Autodesk Fusion 360 part; units mm, degrees
(part 2 of 3)
sketch "草图8 (7)" plane through (0, 0, 8) normal (0, 0, 1) x (1, 0, 0) in component "05_CENTERED_FLAT_PSU_CRADLE_OPEN_INTAKE"
  line L0 (220.4, 198.92) -> (230.4, 198.92)
  line L1 (230.4, 198.92) -> (230.4, 208.92)
  line L2 (230.4, 208.92) -> (220.4, 208.92)
  line L3 (220.4, 208.92) -> (220.4, 198.92)
extrude "Short load foot to ground crossbar (3)" add sketch "草图8 (7)" along normal blind 16 bodies 24 in component "05_CENTERED_FLAT_PSU_CRADLE_OPEN_INTAKE"
ref_plane "工作平面9" through (0, 0, 30) normal (0, 0, 1) x (1, 0, 0) in component "05_CENTERED_FLAT_PSU_CRADLE_OPEN_INTAKE"
sketch "草图9 (7)" plane through (0, 0, 30) normal (0, 0, 1) x (1, 0, 0) in component "05_CENTERED_FLAT_PSU_CRADLE_OPEN_INTAKE"
  line L0 (75, 57.92) -> (77, 57.92)
  line L1 (77, 57.92) -> (77, 63.92)
  line L2 (77, 63.92) -> (75, 63.92)
  line L3 (75, 63.92) -> (75, 57.92)
ref_plane "工作平面10" through (0, 0, 30) normal (0, 0, 1) x (1, 0, 0) in component "05_CENTERED_FLAT_PSU_CRADLE_OPEN_INTAKE"
sketch "草图10 (4)" plane through (0, 0, 30) normal (0, 0, 1) x (1, 0, 0) in component "05_CENTERED_FLAT_PSU_CRADLE_OPEN_INTAKE"
  line L0 (75, 179.92) -> (77, 179.92)
  line L1 (77, 179.92) -> (77, 185.92)
  line L2 (77, 185.92) -> (75, 185.92)
  line L3 (75, 185.92) -> (75, 179.92)
extrude "PSU chassis edge locating stop (1)" add sketch "草图10 (4)" along normal blind 6 bodies 24 in component "05_CENTERED_FLAT_PSU_CRADLE_OPEN_INTAKE"
ref_plane "工作平面11" through (0, 0, 30) normal (0, 0, 1) x (1, 0, 0) in component "05_CENTERED_FLAT_PSU_CRADLE_OPEN_INTAKE"
sketch "草图11 (2)" plane through (0, 0, 30) normal (0, 0, 1) x (1, 0, 0) in component "05_CENTERED_FLAT_PSU_CRADLE_OPEN_INTAKE"
  line L0 (227.8, 57.92) -> (229.8, 57.92)
  line L1 (229.8, 57.92) -> (229.8, 63.92)
  line L2 (229.8, 63.92) -> (227.8, 63.92)
  line L3 (227.8, 63.92) -> (227.8, 57.92)
extrude "PSU chassis edge locating stop (2)" add sketch "草图11 (2)" along normal blind 6 bodies 24 in component "05_CENTERED_FLAT_PSU_CRADLE_OPEN_INTAKE"
ref_plane "工作平面12" through (0, 0, 30) normal (0, 0, 1) x (1, 0, 0) in component "05_CENTERED_FLAT_PSU_CRADLE_OPEN_INTAKE"
sketch "草图12" plane through (0, 0, 30) normal (0, 0, 1) x (1, 0, 0) in component "05_CENTERED_FLAT_PSU_CRADLE_OPEN_INTAKE"
  line L0 (227.8, 179.92) -> (229.8, 179.92)
  line L1 (229.8, 179.92) -> (229.8, 185.92)
  line L2 (229.8, 185.92) -> (227.8, 185.92)
  line L3 (227.8, 185.92) -> (227.8, 179.92)
extrude "PSU chassis edge locating stop (3)" add sketch "草图12" along normal blind 6 bodies 24 in component "05_CENTERED_FLAT_PSU_CRADLE_OPEN_INTAKE"
ref_plane "工作平面1" through (0, 0, 30) normal (0, 0, 1) x (1, 0, 0) in component "REF_PSU_FLAT_CENTERED_150x140x86"
sketch "草图1 (21)" plane through (0, 0, 30) normal (0, 0, 1) x (1, 0, 0) in component "REF_PSU_FLAT_CENTERED_150x140x86"
  line L0 (77.4, 51.92) -> (227.4, 51.92)
  line L1 (227.4, 51.92) -> (227.4, 191.92)
  line L2 (227.4, 191.92) -> (77.4, 191.92)
  line L3 (77.4, 191.92) -> (77.4, 51.92)
extrude "Horizontal PSU 150 wide x140 deep x86 high" add sketch "草图1 (21)" along normal blind 86 separate body makes body 25 in component "REF_PSU_FLAT_CENTERED_150x140x86"
ref_plane "工作平面1" through (0, 0, 29.7) normal (0, 0, 1) x (1, 0, 0) in component "REF_PSU_INTAKE_DOWN_MINUS_Z"
sketch "草图1 (22)" plane through (0, 0, 29.7) normal (0, 0, 1) x (1, 0, 0) in component "REF_PSU_INTAKE_DOWN_MINUS_Z"
  circle A0 centre (152.4, 121.92) radius 60
extrude "Downward-facing 120 mm intake marker - approximate" add sketch "草图1 (22)" along normal blind 0.3 separate body makes body 26 in component "REF_PSU_INTAKE_DOWN_MINUS_Z"
ref_plane "工作平面1" through (0, -191.92, 0) normal (0, 1, 0) x (0, 0, 1) in component "REF_PSU_REAR_EXHAUST_PLUS_Y"
sketch "草图1 (23)" plane through (0, -191.92, 0) normal (0, 1, 0) x (1, 0, 0) in component "REF_PSU_REAR_EXHAUST_PLUS_Y"
  line L0 (77.4, -30, 383.84) -> (227.4, -30, 383.84)
  line L1 (227.4, -30, 383.84) -> (227.4, -116, 383.84)
  line L2 (227.4, -116, 383.84) -> (77.4, -116, 383.84)
  line L3 (77.4, -116, 383.84) -> (77.4, -30, 383.84)
extrude "Rear exhaust face direction marker" add sketch "草图1 (23)" along normal blind 0.3 separate body contours L0 L1 L2 L3 in plane through (0, 191.92, 0) normal (0, 1, 0) makes body 27 in component "REF_PSU_REAR_EXHAUST_PLUS_Y"
ref_plane "工作平面13" through (0, 0, 30) normal (0, 0, 1) x (1, 0, 0) in component "05_CENTERED_FLAT_PSU_CRADLE_OPEN_INTAKE"
sketch "草图13" plane through (0, 0, 30) normal (0, 0, 1) x (1, 0, 0) in component "05_CENTERED_FLAT_PSU_CRADLE_OPEN_INTAKE"
  line L0 (75, 74) -> (77, 74)
  line L1 (77, 74) -> (77, 80)
  line L2 (77, 80) -> (75, 80)
  line L3 (75, 80) -> (75, 74)
extrude "PSU chassis edge locating stop" add sketch "草图13" along normal blind 6 bodies 24 in component "05_CENTERED_FLAT_PSU_CRADLE_OPEN_INTAKE"
ref_plane "工作平面14" through (0, 0, 30) normal (0, 0, 1) x (1, 0, 0) in component "05_CENTERED_FLAT_PSU_CRADLE_OPEN_INTAKE"
sketch "草图14" plane through (0, 0, 30) normal (0, 0, 1) x (1, 0, 0) in component "05_CENTERED_FLAT_PSU_CRADLE_OPEN_INTAKE"
  line L0 (75, 164) -> (77, 164)
  line L1 (77, 164) -> (77, 170)
  line L2 (77, 170) -> (75, 170)
  line L3 (75, 170) -> (75, 164)
extrude "PSU chassis edge locating stop (4)" add sketch "草图14" along normal blind 6 bodies 24 in component "05_CENTERED_FLAT_PSU_CRADLE_OPEN_INTAKE"
ref_plane "工作平面15" through (0, 0, 30) normal (0, 0, 1) x (1, 0, 0) in component "05_CENTERED_FLAT_PSU_CRADLE_OPEN_INTAKE"
sketch "草图15" plane through (0, 0, 30) normal (0, 0, 1) x (1, 0, 0) in component "05_CENTERED_FLAT_PSU_CRADLE_OPEN_INTAKE"
  line L0 (227.8, 74) -> (229.8, 74)
  line L1 (229.8, 74) -> (229.8, 80)
  line L2 (229.8, 80) -> (227.8, 80)
  line L3 (227.8, 80) -> (227.8, 74)
extrude "PSU chassis edge locating stop (5)" add sketch "草图15" along normal blind 6 bodies 24 in component "05_CENTERED_FLAT_PSU_CRADLE_OPEN_INTAKE"
ref_plane "工作平面16" through (0, 0, 30) normal (0, 0, 1) x (1, 0, 0) in component "05_CENTERED_FLAT_PSU_CRADLE_OPEN_INTAKE"
sketch "草图16" plane through (0, 0, 30) normal (0, 0, 1) x (1, 0, 0) in component "05_CENTERED_FLAT_PSU_CRADLE_OPEN_INTAKE"
  line L0 (227.8, 164) -> (229.8, 164)
  line L1 (229.8, 164) -> (229.8, 170)
  line L2 (229.8, 170) -> (227.8, 170)
  line L3 (227.8, 170) -> (227.8, 164)
extrude "PSU chassis edge locating stop (6)" add sketch "草图16" along normal blind 6 bodies 24 in component "05_CENTERED_FLAT_PSU_CRADLE_OPEN_INTAKE"
ref_plane "工作平面1" through (0, 10, 0) normal (0, 1, 0) x (0, 0, 1) in component "12_front_PCI_SUPPORT_FRAME"
sketch "草图1 (24)" plane through (0, 10, 0) normal (0, 1, 0) x (1, 0, 0) in component "12_front_PCI_SUPPORT_FRAME"
  line L0 (8.45, 0, -20) -> (152.1, 0, -20)
  line L1 (152.1, 0, -20) -> (152.1, -140, -20)
  line L2 (152.1, -140, -20) -> (-4, -140, -20)
  line L3 (-4, -140, -20) -> (8.45, 0, -20)
extrude "Front rear load frame" add sketch "草图1 (24)" along normal blind 16 separate body contours L0 L1 L2 L3 in plane through (0, -10, 0) normal (0, 1, 0) makes body 28 in component "12_front_PCI_SUPPORT_FRAME"
ref_plane "工作平面2" through (0, 0, 16) normal (0, 0, 1) x (1, 0, 0) in component "12_front_PCI_SUPPORT_FRAME"
sketch "草图2 (13)" plane through (0, 0, 16) normal (0, 0, 1) x (1, 0, 0) in component "12_front_PCI_SUPPORT_FRAME"
  line L0 (30, -11) -> (134, -11)
  line L1 (134, -11) -> (134, 7)
  line L2 (134, 7) -> (30, 7)
  line L3 (30, 7) -> (30, -11)
extrude "Open front frame window" cut sketch "草图2 (13)" along normal blind 108 bodies 28 in component "12_front_PCI_SUPPORT_FRAME"
ref_plane "工作平面3" through (0, 10, 0) normal (0, 1, 0) x (0, 0, 1) in component "12_front_PCI_SUPPORT_FRAME"
sketch "草图3 (12)" plane through (0, 10, 0) normal (0, 1, 0) x (1, 0, 0) in component "12_front_PCI_SUPPORT_FRAME"
  line L0 (30, -16, -20) -> (42, -16, -20)
  line L1 (42, -16, -20) -> (134, -112, -20)
  line L2 (134, -112, -20) -> (134, -124, -20)
  line L3 (134, -124, -20) -> (30, -16, -20)
extrude "Front diagonal brace" add sketch "草图3 (12)" along normal blind 16 contours L0 L1 L2 L3 in plane through (0, -10, 0) normal (0, 1, 0) bodies 28 in component "12_front_PCI_SUPPORT_FRAME"
ref_plane "工作平面1" through (0, 10, 0) normal (0, 1, 0) x (0, 0, 1) in component "12_front_CPU_SUPPORT_FRAME"
sketch "草图1 (25)" plane through (0, 10, 0) normal (0, 1, 0) x (1, 0, 0) in component "12_front_CPU_SUPPORT_FRAME"
  line L0 (152.7, 0, -20) -> (298.45, 0, -20)
  line L1 (298.45, 0, -20) -> (298.45, -140, -20)
  line L2 (298.45, -140, -20) -> (152.7, -140, -20)
  line L3 (152.7, -140, -20) -> (152.7, 0, -20)
extrude "Front rear load frame'" add sketch "草图1 (25)" along normal blind 16 separate body contours L0 L1 L2 L3 in plane through (0, -10, 0) normal (0, 1, 0) makes body 29 in component "12_front_CPU_SUPPORT_FRAME"
ref_plane "工作平面2" through (0, 0, 16) normal (0, 0, 1) x (1, 0, 0) in component "12_front_CPU_SUPPORT_FRAME"
sketch "草图2 (14)" plane through (0, 0, 16) normal (0, 0, 1) x (1, 0, 0) in component "12_front_CPU_SUPPORT_FRAME"
  line L0 (171, -11) -> (277, -11)
  line L1 (277, -11) -> (277, 7)
  line L2 (277, 7) -> (171, 7)
  line L3 (171, 7) -> (171, -11)
extrude "Open front frame window'" cut sketch "草图2 (14)" along normal blind 108 bodies 29 in component "12_front_CPU_SUPPORT_FRAME"
ref_plane "工作平面3" through (0, 10, 0) normal (0, 1, 0) x (0, 0, 1) in component "12_front_CPU_SUPPORT_FRAME"
sketch "草图3 (13)" plane through (0, 10, 0) normal (0, 1, 0) x (1, 0, 0) in component "12_front_CPU_SUPPORT_FRAME"
  line L0 (171, -16, -20) -> (183, -16, -20)
  line L1 (183, -16, -20) -> (277, -112, -20)
  line L2 (277, -112, -20) -> (277, -124, -20)
  line L3 (277, -124, -20) -> (171, -16, -20)
extrude "Front diagonal brace'" add sketch "草图3 (13)" along normal blind 16 contours L0 L1 L2 L3 in plane through (0, -10, 0) normal (0, 1, 0) bodies 29 in component "12_front_CPU_SUPPORT_FRAME"
ref_plane "工作平面1" through (0, -237.84, 0) normal (0, 1, 0) x (0, 0, 1) in component "12_rear_PCI_SUPPORT_FRAME"
sketch "草图1 (26)" plane through (0, -237.84, 0) normal (0, 1, 0) x (1, 0, 0) in component "12_rear_PCI_SUPPORT_FRAME"
  line L0 (8.45, 0, 475.68) -> (152.1, 0, 475.68)
  line L1 (152.1, 0, 475.68) -> (152.1, -140, 475.68)
  line L2 (152.1, -140, 475.68) -> (-4, -140, 475.68)
  line L3 (-4, -140, 475.68) -> (8.45, 0, 475.68)
extrude "Front rear load frame''" add sketch "草图1 (26)" along normal blind 16 separate body contours L0 L1 L2 L3 in plane through (0, 237.84, 0) normal (0, 1, 0) makes body 30 in component "12_rear_PCI_SUPPORT_FRAME"
ref_plane "工作平面2" through (0, 0, 16) normal (0, 0, 1) x (1, 0, 0) in component "12_rear_PCI_SUPPORT_FRAME"
sketch "草图2 (15)" plane through (0, 0, 16) normal (0, 0, 1) x (1, 0, 0) in component "12_rear_PCI_SUPPORT_FRAME"
  line L0 (30, 236.84) -> (277, 236.84)
  line L1 (277, 236.84) -> (277, 254.84)
  line L2 (277, 254.84) -> (30, 254.84)
  line L3 (30, 254.84) -> (30, 236.84)
extrude "Wide rear exhaust opening" cut sketch "草图2 (15)" along normal blind 109 bodies 30 in component "12_rear_PCI_SUPPORT_FRAME"
ref_plane "工作平面1" through (0, -237.84, 0) normal (0, 1, 0) x (0, 0, 1) in component "12_rear_CPU_SUPPORT_FRAME"
sketch "草图1 (27)" plane through (0, -237.84, 0) normal (0, 1, 0) x (1, 0, 0) in component "12_rear_CPU_SUPPORT_FRAME"
  line L0 (152.7, 0, 475.68) -> (298.45, 0, 475.68)
  line L1 (298.45, 0, 475.68) -> (298.45, -140, 475.68)
  line L2 (298.45, -140, 475.68) -> (152.7, -140, 475.68)
  line L3 (152.7, -140, 475.68) -> (152.7, 0, 475.68)
extrude "Front rear load frame'''" add sketch "草图1 (27)" along normal blind 16 separate body contours L0 L1 L2 L3 in plane through (0, 237.84, 0) normal (0, 1, 0) makes body 31 in component "12_rear_CPU_SUPPORT_FRAME"
ref_plane "工作平面2" through (0, 0, 16) normal (0, 0, 1) x (1, 0, 0) in component "12_rear_CPU_SUPPORT_FRAME"
sketch "草图2 (16)" plane through (0, 0, 16) normal (0, 0, 1) x (1, 0, 0) in component "12_rear_CPU_SUPPORT_FRAME"
  line L0 (30, 236.84) -> (277, 236.84)
  line L1 (277, 236.84) -> (277, 254.84)
  line L2 (277, 254.84) -> (30, 254.84)
  line L3 (30, 254.84) -> (30, 236.84)
extrude "Wide rear exhaust opening'" cut sketch "草图2 (16)" along normal blind 109 bodies 31 in component "12_rear_CPU_SUPPORT_FRAME"
ref_plane "工作平面2" through (0, 0, -0.1) normal (0, 0, 1) x (1, 0, 0) in component "04_front_GROUND_BAR_290mm_FLAT_PSU"
sketch "草图2 (17)" plane through (0, 0, -0.1) normal (0, 0, 1) x (1, 0, 0) in component "04_front_GROUND_BAR_290mm_FLAT_PSU"
  line L0 (8, 20) -> (24.45, 20)
  line L1 (24.45, 20) -> (24.45, 220)
  line L2 (24.45, 220) -> (8, 220)
  line L3 (8, 220) -> (8, 20)
extrude "Butt joint to PCI floor runner" cut sketch "草图2 (17)" along normal blind 8.2 bodies 22 in component "04_front_GROUND_BAR_290mm_FLAT_PSU"
ref_plane "工作平面3" through (0, 0, -0.1) normal (0, 0, 1) x (1, 0, 0) in component "04_front_GROUND_BAR_290mm_FLAT_PSU"
sketch "草图3 (14)" plane through (0, 0, -0.1) normal (0, 0, 1) x (1, 0, 0) in component "04_front_GROUND_BAR_290mm_FLAT_PSU"
  line L0 (282.45, 20) -> (299, 20)
  line L1 (299, 20) -> (299, 220)
  line L2 (299, 220) -> (282.45, 220)
  line L3 (282.45, 220) -> (282.45, 20)
extrude "Butt joint to CPU floor runner" cut sketch "草图3 (14)" along normal blind 8.2 bodies 22 in component "04_front_GROUND_BAR_290mm_FLAT_PSU"
ref_plane "工作平面2" through (0, 0, -0.1) normal (0, 0, 1) x (1, 0, 0) in component "04_rear_GROUND_BAR_290mm_FLAT_PSU"
sketch "草图2 (18)" plane through (0, 0, -0.1) normal (0, 0, 1) x (1, 0, 0) in component "04_rear_GROUND_BAR_290mm_FLAT_PSU"
  line L0 (8, 20) -> (24.45, 20)
  line L1 (24.45, 20) -> (24.45, 220)
  line L2 (24.45, 220) -> (8, 220)
  line L3 (8, 220) -> (8, 20)
extrude "Butt joint to PCI floor runner'" cut sketch "草图2 (18)" along normal blind 8.2 bodies 23 in component "04_rear_GROUND_BAR_290mm_FLAT_PSU"
ref_plane "工作平面3" through (0, 0, -0.1) normal (0, 0, 1) x (1, 0, 0) in component "04_rear_GROUND_BAR_290mm_FLAT_PSU"
sketch "草图3 (15)" plane through (0, 0, -0.1) normal (0, 0, 1) x (1, 0, 0) in component "04_rear_GROUND_BAR_290mm_FLAT_PSU"
  line L0 (282.45, 20) -> (299, 20)
  line L1 (299, 20) -> (299, 220)
  line L2 (299, 220) -> (282.45, 220)
  line L3 (282.45, 220) -> (282.45, 20)
extrude "Butt joint to CPU floor runner'" cut sketch "草图3 (15)" along normal blind 8.2 bodies 23 in component "04_rear_GROUND_BAR_290mm_FLAT_PSU"
ref_plane "工作平面4" through (0, 0, 128) normal (0, 0, 1) x (1, 0, 0) in component "12_front_PCI_SUPPORT_FRAME"
sketch "草图4 (12)" plane through (0, 0, 128) normal (0, 0, 1) x (1, 0, 0) in component "12_front_PCI_SUPPORT_FRAME"
  line L0 (14, -2.65) -> (281.45, -2.65)
  line L1 (281.45, -2.65) -> (281.45, 6.01)
  line L2 (281.45, 6.01) -> (14, 6.01)
  line L3 (14, 6.01) -> (14, -2.65)
extrude "Seat for front motherboard beam rib" cut sketch "草图4 (12)" along normal blind 12.01 bodies 28 in component "12_front_PCI_SUPPORT_FRAME"
ref_plane "工作平面4" through (0, 0, 128) normal (0, 0, 1) x (1, 0, 0) in component "12_front_CPU_SUPPORT_FRAME"
sketch "草图4 (13)" plane through (0, 0, 128) normal (0, 0, 1) x (1, 0, 0) in component "12_front_CPU_SUPPORT_FRAME"
  line L0 (14, -2.65) -> (281.45, -2.65)
  line L1 (281.45, -2.65) -> (281.45, 6.01)
  line L2 (281.45, 6.01) -> (14, 6.01)
  line L3 (14, 6.01) -> (14, -2.65)
extrude "Seat for front motherboard beam rib'" cut sketch "草图4 (13)" along normal blind 12.01 bodies 29 in component "12_front_CPU_SUPPORT_FRAME"
ref_plane "工作平面3" through (0, 0, 128) normal (0, 0, 1) x (1, 0, 0) in component "12_rear_PCI_SUPPORT_FRAME"
sketch "草图3 (16)" plane through (0, 0, 128) normal (0, 0, 1) x (1, 0, 0) in component "12_rear_PCI_SUPPORT_FRAME"
  line L0 (14, 237.83) -> (281.45, 237.83)
  line L1 (281.45, 237.83) -> (281.45, 242.68)
  line L2 (281.45, 242.68) -> (14, 242.68)
  line L3 (14, 242.68) -> (14, 237.83)
extrude "Seat for rear motherboard beam rib" cut sketch "草图3 (16)" along normal blind 12.01 bodies 30 in component "12_rear_PCI_SUPPORT_FRAME"
ref_plane "工作平面3" through (0, 0, 128) normal (0, 0, 1) x (1, 0, 0) in component "12_rear_CPU_SUPPORT_FRAME"
sketch "草图3 (17)" plane through (0, 0, 128) normal (0, 0, 1) x (1, 0, 0) in component "12_rear_CPU_SUPPORT_FRAME"
  line L0 (14, 237.83) -> (281.45, 237.83)
  line L1 (281.45, 237.83) -> (281.45, 242.68)
  line L2 (281.45, 242.68) -> (14, 242.68)
  line L3 (14, 242.68) -> (14, 237.83)
extrude "Seat for rear motherboard beam rib'" cut sketch "草图3 (17)" along normal blind 12.01 bodies 31 in component "12_rear_CPU_SUPPORT_FRAME"
ref_plane "工作平面1" through (0, 0, 140) normal (0, 0, 1) x (1, 0, 0) in component "07_GPU_REINFORCED_REAR_TOWER"
sketch "草图1 (28)" plane through (0, 0, 140) normal (0, 0, 1) x (1, 0, 0) in component "07_GPU_REINFORCED_REAR_TOWER"
  line L0 (70, 244) -> (174, 244)
  line L1 (174, 244) -> (174, 282)
  line L2 (174, 282) -> (70, 282)
  line L3 (70, 282) -> (70, 244)
extrude "Rear frame mounted structural foot" add sketch "草图1 (28)" along normal blind 8 separate body makes body 32 in component "07_GPU_REINFORCED_REAR_TOWER"
ref_plane "工作平面2" through (0, 0, 148) normal (0, 0, 1) x (1, 0, 0) in component "07_GPU_REINFORCED_REAR_TOWER"
sketch "草图2 (19)" plane through (0, 0, 148) normal (0, 0, 1) x (1, 0, 0) in component "07_GPU_REINFORCED_REAR_TOWER"
  line L0 (70, 260) -> (174, 260)
  line L1 (174, 260) -> (174, 270)
  line L2 (174, 270) -> (70, 270)
  line L3 (70, 270) -> (70, 260)
extrude "10 mm rear tower wall" add sketch "草图2 (19)" along normal blind 154 bodies 32 in component "07_GPU_REINFORCED_REAR_TOWER"
ref_plane "工作平面3" through (0, 0, 170) normal (0, 0, 1) x (1, 0, 0) in component "07_GPU_REINFORCED_REAR_TOWER"
sketch "草图3 (18)" plane through (0, 0, 170) normal (0, 0, 1) x (1, 0, 0) in component "07_GPU_REINFORCED_REAR_TOWER"
  line L0 (88, 259.9) -> (156, 259.9)
  line L1 (156, 259.9) -> (156, 270.1)
  line L2 (156, 270.1) -> (88, 270.1)
  line L3 (88, 270.1) -> (88, 259.9)
extrude "Unobstructed display connector window" cut sketch "草图3 (18)" along normal blind 88 bodies 32 in component "07_GPU_REINFORCED_REAR_TOWER"
ref_plane "工作平面4" through (70, 0, 0) normal (1, 0, 0) x (0, 1, 0) in component "07_GPU_REINFORCED_REAR_TOWER"
sketch "草图4 (14)" plane through (70, 0, 0) normal (1, 0, 0) x (0, 0, -1) in component "07_GPU_REINFORCED_REAR_TOWER"
  line L0 (-148, 270) -> (-148, 282)
  line L1 (-148, 282) -> (-212, 270)
  line L2 (-212, 270) -> (-148, 270)
extrude "Tower foot triangular rear gusset" add sketch "草图4 (14)" along normal blind 10 bodies 32 in component "07_GPU_REINFORCED_REAR_TOWER"
ref_plane "工作平面5" through (164, 0, 0) normal (1, 0, 0) x (0, 1, 0) in component "07_GPU_REINFORCED_REAR_TOWER"
sketch "草图5 (11)" plane through (164, 0, 0) normal (1, 0, 0) x (0, 0, -1) in component "07_GPU_REINFORCED_REAR_TOWER"
  line L0 (-148, 270) -> (-148, 282)
  line L1 (-148, 282) -> (-212, 270)
  line L2 (-212, 270) -> (-148, 270)
extrude "Tower foot triangular rear gusset (1)" add sketch "草图5 (11)" along normal blind 10 bodies 32 in component "07_GPU_REINFORCED_REAR_TOWER"
ref_plane "工作平面6" through (0, -260, 0) normal (0, 1, 0) x (0, 0, 1) in component "07_GPU_REINFORCED_REAR_TOWER"
sketch "草图6 (11)" plane through (0, -260, 0) normal (0, 1, 0) x (1, 0, 0) in component "07_GPU_REINFORCED_REAR_TOWER"
  circle A0 through (81.7, -262, 520) (79.15, -260.5278, 520) (79.15, -263.4722, 520)
extrude "Upper carrier height adjustment lower end" cut sketch "草图6 (11)" along normal blind 10 contours A0 in plane through (0, 260, 0) normal (0, 1, 0) bodies 32 in component "07_GPU_REINFORCED_REAR_TOWER"
ref_plane "工作平面7" through (0, -260, 0) normal (0, 1, 0) x (0, 0, 1) in component "07_GPU_REINFORCED_REAR_TOWER"
sketch "草图7 (9)" plane through (0, -260, 0) normal (0, 1, 0) x (1, 0, 0) in component "07_GPU_REINFORCED_REAR_TOWER"
  circle A0 through (81.7, -292, 520) (79.15, -290.5278, 520) (79.15, -293.4722, 520)
extrude "Upper carrier height adjustment upper end" cut sketch "草图7 (9)" along normal blind 10 contours A0 in plane through (0, 260, 0) normal (0, 1, 0) bodies 32 in component "07_GPU_REINFORCED_REAR_TOWER"
ref_plane "工作平面8" through (0, -260, 0) normal (0, 1, 0) x (0, 0, 1) in component "07_GPU_REINFORCED_REAR_TOWER"
sketch "草图8 (8)" plane through (0, -260, 0) normal (0, 1, 0) x (1, 0, 0) in component "07_GPU_REINFORCED_REAR_TOWER"
  line L0 (78.3, -262, 520) -> (81.7, -262, 520)
  line L1 (81.7, -262, 520) -> (81.7, -292, 520)
  line L2 (81.7, -292, 520) -> (78.3, -292, 520)
  line L3 (78.3, -292, 520) -> (78.3, -262, 520)
extrude "Upper carrier height adjustment web" cut sketch "草图8 (8)" along normal blind 10 contours L0 L1 L2 L3 in plane through (0, 260, 0) normal (0, 1, 0) bodies 32 in component "07_GPU_REINFORCED_REAR_TOWER"
ref_plane "工作平面9" through (0, -260, 0) normal (0, 1, 0) x (0, 0, 1) in component "07_GPU_REINFORCED_REAR_TOWER"
sketch "草图9 (8)" plane through (0, -260, 0) normal (0, 1, 0) x (1, 0, 0) in component "07_GPU_REINFORCED_REAR_TOWER"
  circle A0 through (81.7, -151, 520) (79.15, -149.5278, 520) (79.15, -152.4722, 520)
extrude "Lower tab receiver height adjustment lower end" cut sketch "草图9 (8)" along normal blind 10 contours A0 in plane through (0, 260, 0) normal (0, 1, 0) bodies 32 in component "07_GPU_REINFORCED_REAR_TOWER"
ref_plane "工作平面10" through (0, -260, 0) normal (0, 1, 0) x (0, 0, 1) in component "07_GPU_REINFORCED_REAR_TOWER"
sketch "草图10 (5)" plane through (0, -260, 0) normal (0, 1, 0) x (1, 0, 0) in component "07_GPU_REINFORCED_REAR_TOWER"
  circle A0 through (81.7, -165, 520) (79.15, -163.5278, 520) (79.15, -166.4722, 520)
extrude "Lower tab receiver height adjustment upper end" cut sketch "草图10 (5)" along normal blind 10 contours A0 in plane through (0, 260, 0) normal (0, 1, 0) bodies 32 in component "07_GPU_REINFORCED_REAR_TOWER"
ref_plane "工作平面11" through (0, -260, 0) normal (0, 1, 0) x (0, 0, 1) in component "07_GPU_REINFORCED_REAR_TOWER"
sketch "草图11 (3)" plane through (0, -260, 0) normal (0, 1, 0) x (1, 0, 0) in component "07_GPU_REINFORCED_REAR_TOWER"
  line L0 (78.3, -151, 520) -> (81.7, -151, 520)
  line L1 (81.7, -151, 520) -> (81.7, -165, 520)
  line L2 (81.7, -165, 520) -> (78.3, -165, 520)
  line L3 (78.3, -165, 520) -> (78.3, -151, 520)
extrude "Lower tab receiver height adjustment web" cut sketch "草图11 (3)" along normal blind 10 contours L0 L1 L2 L3 in plane through (0, 260, 0) normal (0, 1, 0) bodies 32 in component "07_GPU_REINFORCED_REAR_TOWER"
ref_plane "工作平面12" through (0, -260, 0) normal (0, 1, 0) x (0, 0, 1) in component "07_GPU_REINFORCED_REAR_TOWER"
sketch "草图12 (2)" plane through (0, -260, 0) normal (0, 1, 0) x (1, 0, 0) in component "07_GPU_REINFORCED_REAR_TOWER"
  circle A0 through (165.7, -262, 520) (163.15, -260.5278, 520) (163.15, -263.4722, 520)
extrude "Upper carrier height adjustment lower end (1)" cut sketch "草图12 (2)" along normal blind 10 contours A0 in plane through (0, 260, 0) normal (0, 1, 0) bodies 32 in component "07_GPU_REINFORCED_REAR_TOWER"
ref_plane "工作平面13" through (0, -260, 0) normal (0, 1, 0) x (0, 0, 1) in component "07_GPU_REINFORCED_REAR_TOWER"
sketch "草图13 (2)" plane through (0, -260, 0) normal (0, 1, 0) x (1, 0, 0) in component "07_GPU_REINFORCED_REAR_TOWER"
  circle A0 through (165.7, -292, 520) (163.15, -290.5278, 520) (163.15, -293.4722, 520)
extrude "Upper carrier height adjustment upper end (1)" cut sketch "草图13 (2)" along normal blind 10 contours A0 in plane through (0, 260, 0) normal (0, 1, 0) bodies 32 in component "07_GPU_REINFORCED_REAR_TOWER"
ref_plane "工作平面14" through (0, -260, 0) normal (0, 1, 0) x (0, 0, 1) in component "07_GPU_REINFORCED_REAR_TOWER"
sketch "草图14 (2)" plane through (0, -260, 0) normal (0, 1, 0) x (1, 0, 0) in component "07_GPU_REINFORCED_REAR_TOWER"
  line L0 (162.3, -262, 520) -> (165.7, -262, 520)
  line L1 (165.7, -262, 520) -> (165.7, -292, 520)
  line L2 (165.7, -292, 520) -> (162.3, -292, 520)
  line L3 (162.3, -292, 520) -> (162.3, -262, 520)
extrude "Upper carrier height adjustment web (1)" cut sketch "草图14 (2)" along normal blind 10 contours L0 L1 L2 L3 in plane through (0, 260, 0) normal (0, 1, 0) bodies 32 in component "07_GPU_REINFORCED_REAR_TOWER"
ref_plane "工作平面15" through (0, -260, 0) normal (0, 1, 0) x (0, 0, 1) in component "07_GPU_REINFORCED_REAR_TOWER"
sketch "草图15 (2)" plane through (0, -260, 0) normal (0, 1, 0) x (1, 0, 0) in component "07_GPU_REINFORCED_REAR_TOWER"
  circle A0 through (165.7, -151, 520) (163.15, -149.5278, 520) (163.15, -152.4722, 520)
extrude "Lower tab receiver height adjustment lower end (1)" cut sketch "草图15 (2)" along normal blind 10 contours A0 in plane through (0, 260, 0) normal (0, 1, 0) bodies 32 in component "07_GPU_REINFORCED_REAR_TOWER"
ref_plane "工作平面16" through (0, -260, 0) normal (0, 1, 0) x (0, 0, 1) in component "07_GPU_REINFORCED_REAR_TOWER"
sketch "草图16 (2)" plane through (0, -260, 0) normal (0, 1, 0) x (1, 0, 0) in component "07_GPU_REINFORCED_REAR_TOWER"
  circle A0 through (165.7, -165, 520) (163.15, -163.5278, 520) (163.15, -166.4722, 520)
extrude "Lower tab receiver height adjustment upper end (1)" cut sketch "草图16 (2)" along normal blind 10 contours A0 in plane through (0, 260, 0) normal (0, 1, 0) bodies 32 in component "07_GPU_REINFORCED_REAR_TOWER"
ref_plane "工作平面17" through (0, -260, 0) normal (0, 1, 0) x (0, 0, 1) in component "07_GPU_REINFORCED_REAR_TOWER"
sketch "草图17" plane through (0, -260, 0) normal (0, 1, 0) x (1, 0, 0) in component "07_GPU_REINFORCED_REAR_TOWER"
  line L0 (162.3, -151, 520) -> (165.7, -151, 520)
  line L1 (165.7, -151, 520) -> (165.7, -165, 520)
  line L2 (165.7, -165, 520) -> (162.3, -165, 520)
  line L3 (162.3, -165, 520) -> (162.3, -151, 520)
extrude "Lower tab receiver height adjustment web (1)" cut sketch "草图17" along normal blind 10 contours L0 L1 L2 L3 in plane through (0, 260, 0) normal (0, 1, 0) bodies 32 in component "07_GPU_REINFORCED_REAR_TOWER"
ref_plane "工作平面18" through (0, 0, 140) normal (0, 0, 1) x (1, 0, 0) in component "07_GPU_REINFORCED_REAR_TOWER"
sketch "草图18" plane through (0, 0, 140) normal (0, 0, 1) x (1, 0, 0) in component "07_GPU_REINFORCED_REAR_TOWER"
  circle A0 centre (80, 248.5) radius 1.7
extrude "Rear frame mounting screw clearance" cut sketch "草图18" along normal blind 8 bodies 32 in component "07_GPU_REINFORCED_REAR_TOWER"
ref_plane "工作平面4" through (0, 0, 133.5) normal (0, 0, 1) x (1, 0, 0) in component "12_rear_PCI_SUPPORT_FRAME"
sketch "草图4 (15)" plane through (0, 0, 133.5) normal (0, 0, 1) x (1, 0, 0) in component "12_rear_PCI_SUPPORT_FRAME"
  circle A0 centre (80, 248.5) radius 2.3
extrude "Trial M3 H4.5 OD5 insert pocket" cut sketch "草图4 (15)" along normal blind 6.5 bodies 30 in component "12_rear_PCI_SUPPORT_FRAME"
ref_plane "工作平面19" through (0, 0, 140) normal (0, 0, 1) x (1, 0, 0) in component "07_GPU_REINFORCED_REAR_TOWER"
sketch "草图19" plane through (0, 0, 140) normal (0, 0, 1) x (1, 0, 0) in component "07_GPU_REINFORCED_REAR_TOWER"
  circle A0 centre (140, 248.5) radius 1.7
extrude "Rear frame mounting screw clearance (1)" cut sketch "草图19" along normal blind 8 bodies 32 in component "07_GPU_REINFORCED_REAR_TOWER"
ref_plane "工作平面5" through (0, 0, 133.5) normal (0, 0, 1) x (1, 0, 0) in component "12_rear_PCI_SUPPORT_FRAME"
sketch "草图5 (12)" plane through (0, 0, 133.5) normal (0, 0, 1) x (1, 0, 0) in component "12_rear_PCI_SUPPORT_FRAME"
  circle A0 centre (140, 248.5) radius 2.3
extrude "Trial M3 H4.5 OD5 insert pocket (1)" cut sketch "草图5 (12)" along normal blind 6.5 bodies 30 in component "12_rear_PCI_SUPPORT_FRAME"
ref_plane "工作平面20" through (0, 0, 140) normal (0, 0, 1) x (1, 0, 0) in component "07_GPU_REINFORCED_REAR_TOWER"
sketch "草图20" plane through (0, 0, 140) normal (0, 0, 1) x (1, 0, 0) in component "07_GPU_REINFORCED_REAR_TOWER"
  circle A0 centre (158, 248.5) radius 1.7
extrude "CPU rear frame screw clearance" cut sketch "草图20" along normal blind 8 bodies 32 in component "07_GPU_REINFORCED_REAR_TOWER"
ref_plane "工作平面4" through (0, 0, 133.5) normal (0, 0, 1) x (1, 0, 0) in component "12_rear_CPU_SUPPORT_FRAME"
sketch "草图4 (16)" plane through (0, 0, 133.5) normal (0, 0, 1) x (1, 0, 0) in component "12_rear_CPU_SUPPORT_FRAME"
  circle A0 centre (158, 248.5) radius 2.3
extrude "Trial M3 H4.5 OD5 insert pocket'" cut sketch "草图4 (16)" along normal blind 6.5 bodies 31 in component "12_rear_CPU_SUPPORT_FRAME"
ref_plane "工作平面1" through (0, 0, 260) normal (0, 0, 1) x (1, 0, 0) in component "08_GPU_UPPER_EAR_LEDGE_ADJUSTABLE"
sketch "草图1 (29)" plane through (0, 0, 260) normal (0, 0, 1) x (1, 0, 0) in component "08_GPU_UPPER_EAR_LEDGE_ADJUSTABLE"
  line L0 (74, 254) -> (170, 254)
  line L1 (170, 254) -> (170, 260)
  line L2 (170, 260) -> (74, 260)
  line L3 (74, 260) -> (74, 254)
extrude "Upper sliding mounting plate" add sketch "草图1 (29)" along normal blind 36 separate body makes body 33 in component "08_GPU_UPPER_EAR_LEDGE_ADJUSTABLE"
ref_plane "工作平面2" through (0, 0, 272) normal (0, 0, 1) x (1, 0, 0) in component "08_GPU_UPPER_EAR_LEDGE_ADJUSTABLE"
sketch "草图2 (20)" plane through (0, 0, 272) normal (0, 0, 1) x (1, 0, 0) in component "08_GPU_UPPER_EAR_LEDGE_ADJUSTABLE"
  line L0 (84, 244.84) -> (154, 244.84)
  line L1 (154, 244.84) -> (154, 254)
  line L2 (154, 254) -> (84, 254)
  line L3 (84, 254) -> (84, 244.84)
extrude "10 mm horizontal ear bearing ledge" add sketch "草图2 (20)" along normal blind 10 bodies 33 in component "08_GPU_UPPER_EAR_LEDGE_ADJUSTABLE"
ref_plane "工作平面3" through (84, 0, 0) normal (1, 0, 0) x (0, 1, 0) in component "08_GPU_UPPER_EAR_LEDGE_ADJUSTABLE"
sketch "草图3 (19)" plane through (84, 0, 0) normal (1, 0, 0) x (0, 0, -1) in component "08_GPU_UPPER_EAR_LEDGE_ADJUSTABLE"
  line L0 (-272, 244.84) -> (-262, 254)
  line L1 (-262, 254) -> (-272, 254)
  line L2 (-272, 254) -> (-272, 244.84)
extrude "Under-ledge triangular gusset" add sketch "草图3 (19)" along normal blind 6 bodies 33 in component "08_GPU_UPPER_EAR_LEDGE_ADJUSTABLE"
ref_plane "工作平面4" through (148, 0, 0) normal (1, 0, 0) x (0, 1, 0) in component "08_GPU_UPPER_EAR_LEDGE_ADJUSTABLE"
sketch "草图4 (17)" plane through (148, 0, 0) normal (1, 0, 0) x (0, 0, -1) in component "08_GPU_UPPER_EAR_LEDGE_ADJUSTABLE"
  line L0 (-272, 244.84) -> (-262, 254)
  line L1 (-262, 254) -> (-272, 254)
  line L2 (-272, 254) -> (-272, 244.84)
extrude "Under-ledge triangular gusset (1)" add sketch "草图4 (17)" along normal blind 6 bodies 33 in component "08_GPU_UPPER_EAR_LEDGE_ADJUSTABLE"
ref_plane "工作平面5" through (0, -254, 0) normal (0, 1, 0) x (0, 0, 1) in component "08_GPU_UPPER_EAR_LEDGE_ADJUSTABLE"
sketch "草图5 (13)" plane through (0, -254, 0) normal (0, 1, 0) x (1, 0, 0) in component "08_GPU_UPPER_EAR_LEDGE_ADJUSTABLE"
  circle A0 through (81.7, -276, 508) (79.15, -274.5278, 508) (79.15, -277.4722, 508)
extrude "M3 carrier clamp through hole" cut sketch "草图5 (13)" along normal blind 6 contours A0 in plane through (0, 254, 0) normal (0, 1, 0) bodies 33 in component "08_GPU_UPPER_EAR_LEDGE_ADJUSTABLE"
ref_plane "工作平面6" through (0, -254, 0) normal (0, 1, 0) x (0, 0, 1) in component "08_GPU_UPPER_EAR_LEDGE_ADJUSTABLE"
sketch "草图6 (12)" plane through (0, -254, 0) normal (0, 1, 0) x (1, 0, 0) in component "08_GPU_UPPER_EAR_LEDGE_ADJUSTABLE"
  circle A0 through (165.7, -276, 508) (163.15, -274.5278, 508) (163.15, -277.4722, 508)
extrude "M3 carrier clamp through hole (1)" cut sketch "草图6 (12)" along normal blind 6 contours A0 in plane through (0, 254, 0) normal (0, 1, 0) bodies 33 in component "08_GPU_UPPER_EAR_LEDGE_ADJUSTABLE"
ref_plane "工作平面7" through (0, 0, 275.5) normal (0, 0, 1) x (1, 0, 0) in component "08_GPU_UPPER_EAR_LEDGE_ADJUSTABLE"
sketch "草图7 (10)" plane through (0, 0, 275.5) normal (0, 0, 1) x (1, 0, 0) in component "08_GPU_UPPER_EAR_LEDGE_ADJUSTABLE"
  circle A0 centre (100, 249.5) radius 2.3
extrude "Trial M3 short insert for graphics card ear" cut sketch "草图7 (10)" along normal blind 6.5 bodies 33 in component "08_GPU_UPPER_EAR_LEDGE_ADJUSTABLE"
ref_plane "工作平面8" through (0, 0, 275.5) normal (0, 0, 1) x (1, 0, 0) in component "08_GPU_UPPER_EAR_LEDGE_ADJUSTABLE"
sketch "草图8 (9)" plane through (0, 0, 275.5) normal (0, 0, 1) x (1, 0, 0) in component "08_GPU_UPPER_EAR_LEDGE_ADJUSTABLE"
  circle A0 centre (120, 249.5) radius 2.3
extrude "Trial M3 short insert for graphics card ear (1)" cut sketch "草图8 (9)" along normal blind 6.5 bodies 33 in component "08_GPU_UPPER_EAR_LEDGE_ADJUSTABLE"
ref_plane "工作平面1" through (0, 0, 146) normal (0, 0, 1) x (1, 0, 0) in component "08_GPU_LOWER_TWO_TAB_RECEIVER_ADJUSTABLE"
sketch "草图1 (30)" plane through (0, 0, 146) normal (0, 0, 1) x (1, 0, 0) in component "08_GPU_LOWER_TWO_TAB_RECEIVER_ADJUSTABLE"
  line L0 (74, 254) -> (170, 254)
  line L1 (170, 254) -> (170, 260)
  line L2 (170, 260) -> (74, 260)
  line L3 (74, 260) -> (74, 254)
extrude "Lower sliding receiver back plate" add sketch "草图1 (30)" along normal blind 18 separate body makes body 34 in component "08_GPU_LOWER_TWO_TAB_RECEIVER_ADJUSTABLE"
ref_plane "工作平面2" through (0, 0, 146) normal (0, 0, 1) x (1, 0, 0) in component "08_GPU_LOWER_TWO_TAB_RECEIVER_ADJUSTABLE"
sketch "草图2 (21)" plane through (0, 0, 146) normal (0, 0, 1) x (1, 0, 0) in component "08_GPU_LOWER_TWO_TAB_RECEIVER_ADJUSTABLE"
  line L0 (84, 244.84) -> (140, 244.84)
  line L1 (140, 244.84) -> (140, 254)
  line L2 (140, 254) -> (84, 254)
  line L3 (84, 254) -> (84, 244.84)
extrude "Lower metal tab guide block" add sketch "草图2 (21)" along normal blind 12 bodies 34 in component "08_GPU_LOWER_TWO_TAB_RECEIVER_ADJUSTABLE"
ref_plane "工作平面3" through (0, 0, 145.9) normal (0, 0, 1) x (1, 0, 0) in component "08_GPU_LOWER_TWO_TAB_RECEIVER_ADJUSTABLE"
sketch "草图3 (20)" plane through (0, 0, 145.9) normal (0, 0, 1) x (1, 0, 0) in component "08_GPU_LOWER_TWO_TAB_RECEIVER_ADJUSTABLE"
  line L0 (89, 246.3) -> (103, 246.3)
  line L1 (103, 246.3) -> (103, 248.7)
  line L2 (103, 248.7) -> (89, 248.7)
  line L3 (89, 248.7) -> (89, 246.3)
extrude "Open bottom tab slot - nominal position" cut sketch "草图3 (20)" along normal blind 12.2 bodies 34 in component "08_GPU_LOWER_TWO_TAB_RECEIVER_ADJUSTABLE"
ref_plane "工作平面4" through (0, 0, 145.9) normal (0, 0, 1) x (1, 0, 0) in component "08_GPU_LOWER_TWO_TAB_RECEIVER_ADJUSTABLE"
sketch "草图4 (18)" plane through (0, 0, 145.9) normal (0, 0, 1) x (1, 0, 0) in component "08_GPU_LOWER_TWO_TAB_RECEIVER_ADJUSTABLE"
  line L0 (109, 246.3) -> (123, 246.3)
  line L1 (123, 246.3) -> (123, 248.7)
  line L2 (123, 248.7) -> (109, 248.7)
  line L3 (109, 248.7) -> (109, 246.3)
extrude "Open bottom tab slot - nominal position (1)" cut sketch "草图4 (18)" along normal blind 12.2 bodies 34 in component "08_GPU_LOWER_TWO_TAB_RECEIVER_ADJUSTABLE"
ref_plane "工作平面5" through (0, -254, 0) normal (0, 1, 0) x (0, 0, 1) in component "08_GPU_LOWER_TWO_TAB_RECEIVER_ADJUSTABLE"
sketch "草图5 (14)" plane through (0, -254, 0) normal (0, 1, 0) x (1, 0, 0) in component "08_GPU_LOWER_TWO_TAB_RECEIVER_ADJUSTABLE"
  circle A0 through (81.7, -157, 508) (79.15, -155.5278, 508) (79.15, -158.4722, 508)
extrude "M3 lower receiver clamp through hole" cut sketch "草图5 (14)" along normal blind 6 contours A0 in plane through (0, 254, 0) normal (0, 1, 0) bodies 34 in component "08_GPU_LOWER_TWO_TAB_RECEIVER_ADJUSTABLE"
ref_plane "工作平面6" through (0, -254, 0) normal (0, 1, 0) x (0, 0, 1) in component "08_GPU_LOWER_TWO_TAB_RECEIVER_ADJUSTABLE"
sketch "草图6 (13)" plane through (0, -254, 0) normal (0, 1, 0) x (1, 0, 0) in component "08_GPU_LOWER_TWO_TAB_RECEIVER_ADJUSTABLE"
  circle A0 through (165.7, -157, 508) (163.15, -155.5278, 508) (163.15, -158.4722, 508)
extrude "M3 lower receiver clamp through hole (1)" cut sketch "草图6 (13)" along normal blind 6 contours A0 in plane through (0, 254, 0) normal (0, 1, 0) bodies 34 in component "08_GPU_LOWER_TWO_TAB_RECEIVER_ADJUSTABLE"
ref_plane "工作平面7" through (0, 0, 145.9) normal (0, 0, 1) x (1, 0, 0) in component "08_GPU_LOWER_TWO_TAB_RECEIVER_ADJUSTABLE"
sketch "草图7 (11)" plane through (0, 0, 145.9) normal (0, 0, 1) x (1, 0, 0) in component "08_GPU_LOWER_TWO_TAB_RECEIVER_ADJUSTABLE"
  line L0 (73, 244) -> (171, 244)
  line L1 (171, 244) -> (171, 260.1)
  line L2 (171, 260.1) -> (73, 260.1)
  line L3 (73, 260.1) -> (73, 244)
extrude "Receiver clearance above structural foot" cut sketch "草图7 (11)" along normal blind 2.1 bodies 34 in component "08_GPU_LOWER_TWO_TAB_RECEIVER_ADJUSTABLE"
ref_plane "工作平面21" through (0, 0, 139.9) normal (0, 0, 1) x (1, 0, 0) in component "07_GPU_REINFORCED_REAR_TOWER"
sketch "草图21" plane through (0, 0, 139.9) normal (0, 0, 1) x (1, 0, 0) in component "07_GPU_REINFORCED_REAR_TOWER"
  line L0 (89, 246.3) -> (103, 246.3)
  line L1 (103, 246.3) -> (103, 248.7)
  line L2 (103, 248.7) -> (89, 248.7)
  line L3 (89, 248.7) -> (89, 246.3)
extrude "Through foot clearance below GPU metal tabs" cut sketch "草图21" along normal blind 8.2 bodies 32 in component "07_GPU_REINFORCED_REAR_TOWER"
ref_plane "工作平面6" through (0, 0, 124.9) normal (0, 0, 1) x (1, 0, 0) in component "12_rear_PCI_SUPPORT_FRAME"
sketch "草图6 (14)" plane through (0, 0, 124.9) normal (0, 0, 1) x (1, 0, 0) in component "12_rear_PCI_SUPPORT_FRAME"
  line L0 (89, 246.3) -> (103, 246.3)
  line L1 (103, 246.3) -> (103, 248.7)
  line L2 (103, 248.7) -> (89, 248.7)
  line L3 (89, 248.7) -> (89, 246.3)
extrude "Open metal tab exit through rear frame" cut sketch "草图6 (14)" along normal blind 15.2 bodies 30 in component "12_rear_PCI_SUPPORT_FRAME"
ref_plane "工作平面22" through (0, 0, 139.9) normal (0, 0, 1) x (1, 0, 0) in component "07_GPU_REINFORCED_REAR_TOWER"
sketch "草图22" plane through (0, 0, 139.9) normal (0, 0, 1) x (1, 0, 0) in component "07_GPU_REINFORCED_REAR_TOWER"
  line L0 (109, 246.3) -> (123, 246.3)
  line L1 (123, 246.3) -> (123, 248.7)
  line L2 (123, 248.7) -> (109, 248.7)
  line L3 (109, 248.7) -> (109, 246.3)
extrude "Through foot clearance below GPU metal tabs (1)" cut sketch "草图22" along normal blind 8.2 bodies 32 in component "07_GPU_REINFORCED_REAR_TOWER"
ref_plane "工作平面7" through (0, 0, 124.9) normal (0, 0, 1) x (1, 0, 0) in component "12_rear_PCI_SUPPORT_FRAME"
sketch "草图7 (12)" plane through (0, 0, 124.9) normal (0, 0, 1) x (1, 0, 0) in component "12_rear_PCI_SUPPORT_FRAME"
  line L0 (109, 246.3) -> (123, 246.3)
  line L1 (123, 246.3) -> (123, 248.7)
  line L2 (123, 248.7) -> (109, 248.7)
  line L3 (109, 248.7) -> (109, 246.3)
extrude "Open metal tab exit through rear frame (1)" cut sketch "草图7 (12)" along normal blind 15.2 bodies 30 in component "12_rear_PCI_SUPPORT_FRAME"
ref_plane "工作平面8" through (0, 0, 0) normal (0, 0, 1) x (1, 0, 0) in component "12_rear_PCI_SUPPORT_FRAME"
sketch "草图8 (10)" plane through (0, 0, 0) normal (0, 0, 1) x (1, 0, 0) in component "12_rear_PCI_SUPPORT_FRAME"
  line L0 (-10, 237) -> (310, 237)
  line L1 (310, 237) -> (310, 255)
  line L2 (310, 255) -> (-10, 255)
  line L3 (-10, 255) -> (-10, 237)
extrude "Remove rear vertical and bottom frame" cut sketch "草图8 (10)" along normal blind 125 bodies 30 in component "12_rear_PCI_SUPPORT_FRAME"
ref_plane "工作平面5" through (0, 0, 0) normal (0, 0, 1) x (1, 0, 0) in component "12_rear_CPU_SUPPORT_FRAME"
sketch "草图5 (15)" plane through (0, 0, 0) normal (0, 0, 1) x (1, 0, 0) in component "12_rear_CPU_SUPPORT_FRAME"
  line L0 (-10, 237) -> (310, 237)
  line L1 (310, 237) -> (310, 255)
  line L2 (310, 255) -> (-10, 255)
  line L3 (-10, 255) -> (-10, 237)
extrude "Remove rear vertical and bottom frame'" cut sketch "草图5 (15)" along normal blind 125 bodies 31 in component "12_rear_CPU_SUPPORT_FRAME"
ref_plane "工作平面9" through (0, 0, 124.9) normal (0, 0, 1) x (1, 0, 0) in component "12_rear_PCI_SUPPORT_FRAME"
sketch "草图9 (9)" plane through (0, 0, 124.9) normal (0, 0, 1) x (1, 0, 0) in component "12_rear_PCI_SUPPORT_FRAME"
  line L0 (-10, 237) -> (24.45, 237)
  line L1 (24.45, 237) -> (24.45, 255)
  line L2 (24.45, 255) -> (-10, 255)
  line L3 (-10, 255) -> (-10, 237)
extrude "Rear beam butt joint to PCI side" cut sketch "草图9 (9)" along normal blind 15.2 bodies 30 in component "12_rear_PCI_SUPPORT_FRAME"
ref_plane "工作平面6" through (0, 0, 124.9) normal (0, 0, 1) x (1, 0, 0) in component "12_rear_CPU_SUPPORT_FRAME"
sketch "草图6 (15)" plane through (0, 0, 124.9) normal (0, 0, 1) x (1, 0, 0) in component "12_rear_CPU_SUPPORT_FRAME"
  line L0 (282.45, 237) -> (310, 237)
  line L1 (310, 237) -> (310, 255)
  line L2 (310, 255) -> (282.45, 255)
  line L3 (282.45, 255) -> (282.45, 237)
extrude "Rear beam butt joint to CPU side" cut sketch "草图6 (15)" along normal blind 15.2 bodies 31 in component "12_rear_CPU_SUPPORT_FRAME"
ref_plane "工作平面1" through (0, 0, 0) normal (0, 0, 1) x (1, 0, 0) in component "16_CPU_VERTICAL_SIDE_SUPPORT"
sketch "草图1 (31)" plane through (0, 0, 0) normal (0, 0, 1) x (1, 0, 0) in component "16_CPU_VERTICAL_SIDE_SUPPORT"
  line L0 (282.45, 6) -> (298.45, 6)
  line L1 (298.45, 6) -> (298.45, 253.84)
  line L2 (298.45, 253.84) -> (282.45, 253.84)
  line L3 (282.45, 253.84) -> (282.45, 6)
extrude "CPU side vertical frame" add sketch "草图1 (31)" along normal blind 140 separate body makes body 35 in component "16_CPU_VERTICAL_SIDE_SUPPORT"
ref_plane "工作平面2" through (0, 0, 16) normal (0, 0, 1) x (1, 0, 0) in component "16_CPU_VERTICAL_SIDE_SUPPORT"
sketch "草图2 (22)" plane through (0, 0, 16) normal (0, 0, 1) x (1, 0, 0) in component "16_CPU_VERTICAL_SIDE_SUPPORT"
  line L0 (282.3, 22) -> (298.6, 22)
  line L1 (298.6, 22) -> (298.6, 237.84)
  line L2 (298.6, 237.84) -> (282.3, 237.84)
  line L3 (282.3, 237.84) -> (282.3, 22)
extrude "CPU side open window" cut sketch "草图2 (22)" along normal blind 108 bodies 35 in component "16_CPU_VERTICAL_SIDE_SUPPORT"
ref_plane "工作平面3" through (282.45, 0, 0) normal (1, 0, 0) x (0, 1, 0) in component "16_CPU_VERTICAL_SIDE_SUPPORT"
sketch "草图3 (21)" plane through (282.45, 0, 0) normal (1, 0, 0) x (0, 0, -1) in component "16_CPU_VERTICAL_SIDE_SUPPORT"
  line L0 (-16, 22) -> (-16, 38)
  line L1 (-16, 38) -> (-108, 237.84)
  line L2 (-108, 237.84) -> (-124, 237.84)
  line L3 (-124, 237.84) -> (-16, 22)
extrude "CPU side diagonal" add sketch "草图3 (21)" along normal blind 16 bodies 35 in component "16_CPU_VERTICAL_SIDE_SUPPORT"
ref_plane "工作平面1" through (0, -6, 0) normal (0, 1, 0) x (0, 0, 1) in component "16_PCI_INSET_SIDE_SUPPORT"
sketch "草图1 (32)" plane through (0, -6, 0) normal (0, 1, 0) x (1, 0, 0) in component "16_PCI_INSET_SIDE_SUPPORT"
  line L0 (8.45, 0, 12) -> (24.45, 0, 12)
  line L1 (24.45, 0, 12) -> (12, -140, 12)
  line L2 (12, -140, 12) -> (-4, -140, 12)
  line L3 (-4, -140, 12) -> (8.45, 0, 12)
extrude "PCI side inset 12.45 mm" add sketch "草图1 (32)" along normal blind 247.84 separate body contours L0 L1 L2 L3 in plane through (0, 6, 0) normal (0, 1, 0) makes body 36 in component "16_PCI_INSET_SIDE_SUPPORT"
ref_plane "工作平面2" through (0, 0, 16) normal (0, 0, 1) x (1, 0, 0) in component "16_PCI_INSET_SIDE_SUPPORT"
sketch "草图2 (23)" plane through (0, 0, 16) normal (0, 0, 1) x (1, 0, 0) in component "16_PCI_INSET_SIDE_SUPPORT"
  line L0 (-4.1, 22) -> (24.6, 22)
  line L1 (24.6, 22) -> (24.6, 237.84)
  line L2 (24.6, 237.84) -> (-4.1, 237.84)
  line L3 (-4.1, 237.84) -> (-4.1, 22)
extrude "PCI side open window" cut sketch "草图2 (23)" along normal blind 108 bodies 36 in component "16_PCI_INSET_SIDE_SUPPORT"
ref_plane "工作平面3" through (-4, 0, 0) normal (1, 0, 0) x (0, 1, 0) in component "16_PCI_INSET_SIDE_SUPPORT"
sketch "草图3 (22)" plane through (-4, 0, 0) normal (1, 0, 0) x (0, 0, -1) in component "16_PCI_INSET_SIDE_SUPPORT"
  line L0 (-16, 22) -> (-16, 38)
  line L1 (-16, 38) -> (-108, 237.84)
  line L2 (-108, 237.84) -> (-124, 237.84)
  line L3 (-124, 237.84) -> (-16, 22)
extrude "PCI side diagonal before taper trim" add sketch "草图3 (22)" along normal blind 28.45 bodies 36 in component "16_PCI_INSET_SIDE_SUPPORT"
ref_plane "工作平面4" through (0, -5.9, 0) normal (0, 1, 0) x (0, 0, 1) in component "16_PCI_INSET_SIDE_SUPPORT"
sketch "草图4 (19)" plane through (0, -5.9, 0) normal (0, 1, 0) x (1, 0, 0) in component "16_PCI_INSET_SIDE_SUPPORT"
  line L0 (-10, 0, 11.8) -> (8.45, 0, 11.8)
  line L1 (8.45, 0, 11.8) -> (-4, -140, 11.8)
  line L2 (-4, -140, 11.8) -> (-10, -140, 11.8)
  line L3 (-10, -140, 11.8) -> (-10, 0, 11.8)
extrude "Trim diagonal to outer tapered face" cut sketch "草图4 (19)" along normal blind 248.1 contours L0 L1 L2 L3 in plane through (0, 5.9, 0) normal (0, 1, 0) bodies 36 in component "16_PCI_INSET_SIDE_SUPPORT"
ref_plane "工作平面5" through (0, -5.9, 0) normal (0, 1, 0) x (0, 0, 1) in component "16_PCI_INSET_SIDE_SUPPORT"
sketch "草图5 (16)" plane through (0, -5.9, 0) normal (0, 1, 0) x (1, 0, 0) in component "16_PCI_INSET_SIDE_SUPPORT"
  line L0 (24.45, 0, 11.8) -> (40, 0, 11.8)
  line L1 (40, 0, 11.8) -> (40, -140, 11.8)
  line L2 (40, -140, 11.8) -> (12, -140, 11.8)
  line L3 (12, -140, 11.8) -> (24.45, 0, 11.8)
extrude "Trim diagonal to inner tapered face" cut sketch "草图5 (16)" along normal blind 248.1 contours L0 L1 L2 L3 in plane through (0, 5.9, 0) normal (0, 1, 0) bodies 36 in component "16_PCI_INSET_SIDE_SUPPORT"
ref_plane "工作平面1" through (0, 0, 126) normal (0, 0, 1) x (1, 0, 0) in component "17_REAR_TOP_BEAM_SEAM_JOINER"
sketch "草图1 (33)" plane through (0, 0, 126) normal (0, 0, 1) x (1, 0, 0) in component "17_REAR_TOP_BEAM_SEAM_JOINER"
  line L0 (132, 253.84) -> (176, 253.84)
  line L1 (176, 253.84) -> (176, 257.84)
  line L2 (176, 257.84) -> (132, 257.84)
  line L3 (132, 257.84) -> (132, 253.84)
extrude "Rear top beam seam bridge" add sketch "草图1 (33)" along normal blind 12 separate body makes body 37 in component "17_REAR_TOP_BEAM_SEAM_JOINER"
ref_plane "工作平面2" through (0, -253.84, 0) normal (0, 1, 0) x (0, 0, 1) in component "17_REAR_TOP_BEAM_SEAM_JOINER"
sketch "草图2 (24)" plane through (0, -253.84, 0) normal (0, 1, 0) x (1, 0, 0) in component "17_REAR_TOP_BEAM_SEAM_JOINER"
  circle A0 through (141.7, -132, 507.68) (139.15, -130.5278, 507.68) (139.15, -133.4722, 507.68)
extrude "M3 seam bridge clearance" cut sketch "草图2 (24)" along normal blind 4 contours A0 in plane through (0, 253.84, 0) normal (0, 1, 0) bodies 37 in component "17_REAR_TOP_BEAM_SEAM_JOINER"
ref_plane "工作平面10" through (0, -247.34, 0) normal (0, 1, 0) x (0, 0, 1) in component "12_rear_PCI_SUPPORT_FRAME"
sketch "草图10 (6)" plane through (0, -247.34, 0) normal (0, 1, 0) x (1, 0, 0) in component "12_rear_PCI_SUPPORT_FRAME"
  circle A0 through (142.3, -132, 494.68) (138.85, -130.0081, 494.68) (138.85, -133.9919, 494.68)
extrude "Trial short insert for rear beam bridge" cut sketch "草图10 (6)" along normal blind 6.5 contours A0 in plane through (0, 247.34, 0) normal (0, 1, 0) bodies 30 in component "12_rear_PCI_SUPPORT_FRAME"
ref_plane "工作平面3" through (0, -253.84, 0) normal (0, 1, 0) x (0, 0, 1) in component "17_REAR_TOP_BEAM_SEAM_JOINER"
sketch "草图3 (23)" plane through (0, -253.84, 0) normal (0, 1, 0) x (1, 0, 0) in component "17_REAR_TOP_BEAM_SEAM_JOINER"
  circle A0 through (165.7, -132, 507.68) (163.15, -130.5278, 507.68) (163.15, -133.4722, 507.68)
extrude "M3 seam bridge clearance (1)" cut sketch "草图3 (23)" along normal blind 4 contours A0 in plane through (0, 253.84, 0) normal (0, 1, 0) bodies 37 in component "17_REAR_TOP_BEAM_SEAM_JOINER"
ref_plane "工作平面7" through (0, -247.34, 0) normal (0, 1, 0) x (0, 0, 1) in component "12_rear_CPU_SUPPORT_FRAME"
sketch "草图7 (13)" plane through (0, -247.34, 0) normal (0, 1, 0) x (1, 0, 0) in component "12_rear_CPU_SUPPORT_FRAME"
  circle A0 through (166.3, -132, 494.68) (162.85, -130.0081, 494.68) (162.85, -133.9919, 494.68)
extrude "Trial short insert for rear beam bridge'" cut sketch "草图7 (13)" along normal blind 6.5 contours A0 in plane through (0, 247.34, 0) normal (0, 1, 0) bodies 31 in component "12_rear_CPU_SUPPORT_FRAME"
ref_plane "工作平面12" through (0, 0, 0) normal (0, 0, 1) x (1, 0, 0) in component "03_FRONT_MOTHERBOARD_BEAM"
sketch "草图12 (3)" plane through (0, 0, 0) normal (0, 0, 1) x (1, 0, 0) in component "03_FRONT_MOTHERBOARD_BEAM"
  line L0 (302.45, -20) -> (312, -20)
  line L1 (312, -20) -> (312, 260)
  line L2 (312, 260) -> (302.45, 260)
  line L3 (302.45, 260) -> (302.45, -20)
extrude "Trim CPU beam end flush with mounting boss tangent" cut sketch "草图12 (3)" along normal blind 220 bodies 1 in component "03_FRONT_MOTHERBOARD_BEAM"
ref_plane "工作平面10" through (0, 0, 0) normal (0, 0, 1) x (1, 0, 0) in component "03_MID_MOTHERBOARD_BEAM"
sketch "草图10 (7)" plane through (0, 0, 0) normal (0, 0, 1) x (1, 0, 0) in component "03_MID_MOTHERBOARD_BEAM"
  line L0 (302.45, -20) -> (312, -20)
  line L1 (312, -20) -> (312, 260)
  line L2 (312, 260) -> (302.45, 260)
  line L3 (302.45, 260) -> (302.45, -20)
extrude "Trim CPU beam end flush with mounting boss tangent'" cut sketch "草图10 (7)" along normal blind 220 bodies 2 in component "03_MID_MOTHERBOARD_BEAM"
ref_plane "工作平面11" through (0, 0, 0) normal (0, 0, 1) x (1, 0, 0) in component "03_REAR_MOTHERBOARD_BEAM"
sketch "草图11 (4)" plane through (0, 0, 0) normal (0, 0, 1) x (1, 0, 0) in component "03_REAR_MOTHERBOARD_BEAM"
  line L0 (302.45, -20) -> (312, -20)
  line L1 (312, -20) -> (312, 260)
  line L2 (312, 260) -> (302.45, 260)
  line L3 (302.45, 260) -> (302.45, -20)
extrude "Trim CPU beam end flush with mounting boss tangent''" cut sketch "草图11 (4)" along normal blind 220 bodies 3 in component "03_REAR_MOTHERBOARD_BEAM"
component "03_FRONT_MOTHERBOARD_BEAM" placed x (1, 0, 0) y (0, 1, 0) z (0, 0, 1) at (0, 0, -50)
component "03_MID_MOTHERBOARD_BEAM" placed x (1, 0, 0) y (0, 1, 0) z (0, 0, 1) at (0, 0, -50)
component "03_REAR_MOTHERBOARD_BEAM" placed x (1, 0, 0) y (0, 1, 0) z (0, 0, 1) at (0, 0, -50)
component "09_FRONT_DUAL_FAN_CARRIER" placed x (1, 0, 0) y (0, 1, 0) z (0, 0, 1) at (0, 0, -50)
component "10_GPU_140_FAN_MOUNT" placed x (1, 0, 0) y (0, 1, 0) z (0, 0, 1) at (0, 0, -50)
component "10_CPU_140_FAN_MOUNT" placed x (1, 0, 0) y (0, 1, 0) z (0, 0, 1) at (0, 0, -50)
component "REF_CASE_FAN_GPU_140x140x25" placed x (1, 0, 0) y (0, 1, 0) z (0, 0, 1) at (0, 0, -50)
component "REF_AIRFLOW_GPU_FRONT_TO_REAR" placed x (1, 0, 0) y (0, 1, 0) z (0, 0, 1) at (0, 0, -50)